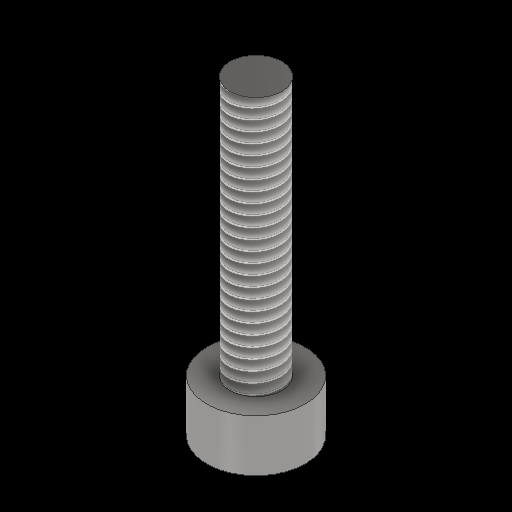
# Autodesk Inventor part: M2 x 10 mm Schraube
Saved by Autodesk Inventor 2027.1 (Build 311270010, 270A)
## iProperties
Created: 2026-10-15
Part Number: M2 x 10 mm Schraube
Material: Generisch
Document SubType Name: Modeling
Designer: josia
Density: 1 g/cm^3
Appearance: Stahl - poliert
Author: josia
Autodesk Inventor part; units mm, degrees
ref_plane "YZ Plane" through (0, 0, 0) normal (1, 0, 0) x (0, 1, 0)
ref_plane "XZ Plane" through (0, 0, 0) normal (0, 1, 0) x (-1, 0, 0)
ref_plane "XY Plane" through (0, 0, 0) normal (0, 0, 1) x (1, 0, 0)
sketch "Skizze1" plane through (0, 0, 0) normal (0, 1, 0) x (-1, 0, 0)
  circle A0 centre (0, 0) radius 1.9
  dimension "d0" = 3.8
  constraints: 1 centre point, 1 coincident
  measures "d0" diameter of A0
extrude "Extrusion1" add sketch "Skizze1" along normal blind 2
sketch "Skizze2" plane through (0, 2, 0) normal (0, 1, 0) x (1, 0, 0)
  circle A0 centre (0, 0) radius 1
  dimension "d3" = 2
  constraints: 1 centre point, 1 coincident
  measures "d3" diameter of A0
extrude "Extrusion2" add sketch "Skizze2" along normal blind 10
sketch "Skizze3" plane through (0, 0, 0) normal (0, -1, 0) x (1, 0, 0)
  circle A0 centre (0, 0) radius 1.9 projected
  line L0 (1, -0.5329) -> (0.0385, -1.1325)
  line L1 (0.0385, -1.1325) -> (-0.9615, -0.5996)
  line L2 (-0.9615, -0.5996) -> (-1, 0.5329)
  line L3 (-1, 0.5329) -> (-0.0385, 1.1325)
  line L4 (-0.0385, 1.1325) -> (0.9615, 0.5996)
  line L5 (0.9615, 0.5996) -> (1, -0.5329)
  constraints: 12 end point, 1 coincident, 13 other
extrude "Extrusion3" cut sketch "Skizze3" against normal blind 1 contours L0 L1 L2 L3 L4 L5
thread "Gewinde1" size "M2x0.4" class "6g" standard "ANSI Metric M Profile" length 14
